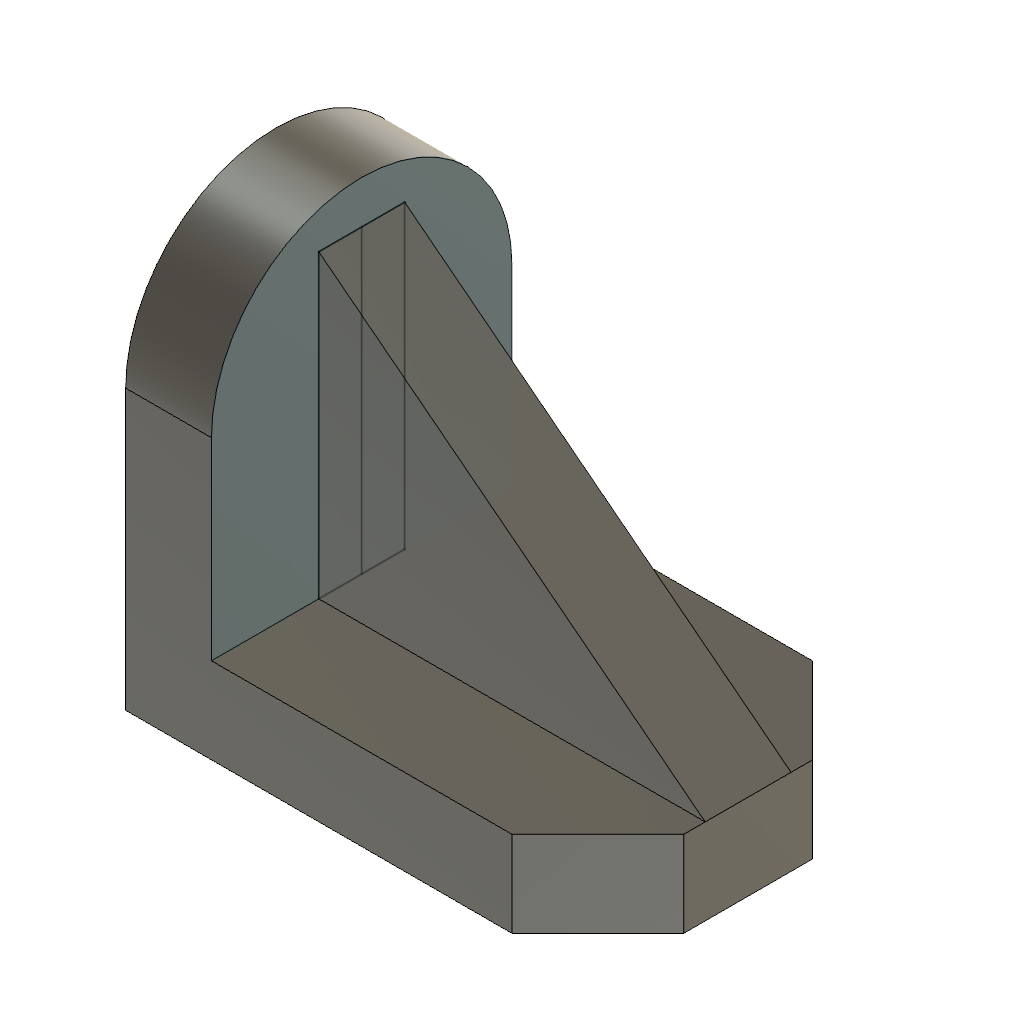
3D_1 (Autodesk Fusion 360 design; units mm, degrees)
part number: 2026-09-30-13-57-32-365
Autodesk Fusion 360 part; units mm, degrees
sketch "Sketch1" plane through (0, 0, 0) normal (0, 0, 1) x (1, 0, 0)
  line L0 (21, 21) -> (-33, 21)
  line L1 (-33, 21) -> (-33, -21)
  line L2 (-33, -21) -> (21, -21)
  line L3 (33, -9) -> (33, 9)
  line L4 (33, 21) -> (-33, -21) construction
  line L5 (-33, 21) -> (33, -21) construction
  line L6 (21, -21) -> (33, -9)
  line L7 (34.2032, 45.3294) -> (124.4495, 45.3294)
  line L8 (33, 9) -> (21, 21)
  dimension "d1" = 66
  dimension "d2" = 42
  dimension "d3" = 12
  dimension "d4" = 12
  dimension "d5" = 12
  dimension "d6" = 12
  constraint horizontal L0
  constraint perpendicular L0 L1
  constraint parallel L0 L2
  constraint parallel L1 L3
  constraint coincident L4 origin
  constraint coincident L5 origin
  constraint coincident L5.end L2
  constraint coincident L5.end L3
  constraint horizontal L7
  constraint coincident L4.start L3
  constraint coincident L4.start L0
  measures "d1" distance of L1.end L5.end
  measures "d2" distance of L0.end L1.end
  measures "d3" distance of L5.end L2.end
  measures "d4" distance of L5.end L3.start
  measures "d5" distance of L4.start L3.end
  measures "d6" distance of L4.start L0.start
extrude "Extrude1" add sketch "Sketch1" along normal blind 12
sketch "Sketch2" plane through (0, 0, 12) normal (0, 0, 1) x (-1, 0, 0)
  line L0 (-33, -9) -> (-21, -21)
  line L1 (-21, -21) -> (33, -21)
  line L2 (33, -21) -> (33, 21)
  line L3 (33, 21) -> (-21, 21)
  line L4 (-21, 21) -> (-33, 9)
  line L5 (-33, 9) -> (-33, -9)
  line L6 (33, -21) -> (21, -21)
  line L7 (21, -21) -> (21, 21)
  line L8 (21, 21) -> (33, 21)
  line L9 (33, 21) -> (33, -21)
  dimension "d9" = 12
  constraint horizontal L6
  constraint vertical L7
  constraint horizontal L8
  constraint vertical L9
  constraint coincident L3 L7.end
  constraint coincident L1.end L2.start
  measures "d9" distance of L7 L9
extrude "Extrude2" add sketch "Sketch2" along normal blind 48 contours L1 L2 L3 L6 L7 L8 L9
fillet "Fillet1" radius 21 2 edges at (-27, -21, 60) (-27, 21, 60)
sketch "Sketch4" plane through (-21, 0, 0) normal (1, 0, 0) x (0, 1, 0)
  arc A0 (21, 39) -> (-21, 39) centre (0, 39) ccw
  line L0 (-21, 39) -> (-21, 12)
  line L1 (-21, 12) -> (21, 12)
  line L2 (21, 12) -> (21, 39)
  line L3 (-6, 54) -> (6, 54)
  line L4 (6, 54) -> (6, 12)
  line L5 (6, 12) -> (-6, 12)
  line L6 (-6, 12) -> (-6, 54)
  line L7 (0, 12) -> (0, 54)
  dimension "d17" = 12
  dimension "d18" = 42
  constraint horizontal L3
  constraint vertical L4
  constraint horizontal L5
  constraint vertical L6
  constraint midpoint L1 L5
  constraint midpoint L5 L7.start
  constraint midpoint L3 L7.end
  measures "d17" distance of L3.start L3.end
  measures "d18" distance of L3.start L5.end
sketch "Sketch5" plane through (0, 0, 12) normal (0, 0, 1) x (-1, 0, 0)
  line L0 (21, -21) -> (21, 21)
  line L1 (21, 21) -> (-21, 21)
  line L2 (-21, 21) -> (-33, 9)
  line L3 (-33, 9) -> (-33, -9)
  line L4 (-33, -9) -> (-21, -21)
  line L5 (-21, -21) -> (21, -21)
  line L6 (21, -6) -> (-33, -6)
  line L7 (-33, -6) -> (-33, 6)
  line L8 (-33, 6) -> (21, 6)
  line L9 (21, 6) -> (21, -6)
  dimension "d19" = 12
  dimension "d20" = 15
  constraint horizontal L6
  constraint vertical L7
  constraint horizontal L8
  constraint vertical L9
  constraint coincident L0 L6.start
  measures "d19" distance of L6.start L8.end
  measures "d20" distance of L1 L8
extrude "Extrude3" add sketch "Sketch5" along normal blind 42 contours L0 L3 L6 L7 L8 L9
sketch "Sketch7" plane through (0, -6, 0) normal (0, -1, 0) x (1, 0, 0)
  line L0 (-21, 12) -> (33, 12)
  line L1 (33, 12) -> (33, 54)
  line L2 (33, 54) -> (-21, 54)
  line L3 (-21, 54) -> (-21, 12)
  line L4 (-21, 54) -> (33, 12)
  constraint coincident L2.end L3.start
  constraint coincident L0.end L1.start
extrude "Extrude4" cut sketch "Sketch7" against normal blind 20 contours L1 L2 L4
equation "d4 = d3"
equation "d6 = d5"
equation "d10 = 60 mm - 12 mm"
